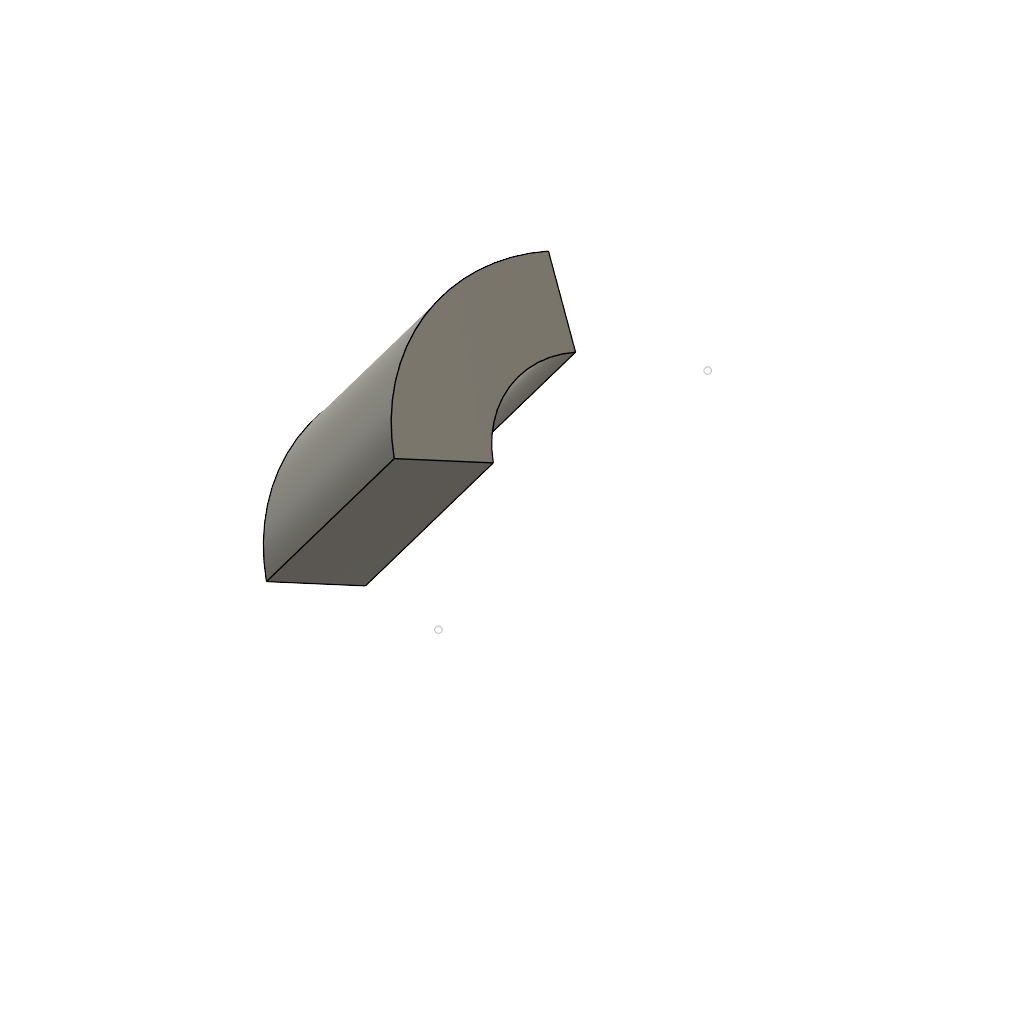
direction_restored (Autodesk Fusion 360 design; units mm, degrees)
part number: 2026-11-27-16-03-31-914
Autodesk Fusion 360 part; units mm, degrees
sketch "AxisSupport" plane through (0, 0, 0) normal (0, 0, 1) x (1, 0, 0)
  point P0 (11, -7)
  point P1 (35, 25)
sketch "RevolveProfile" plane through (0, 0, 0) normal (0, 0, 1) x (1, 0, 0)
  line L0 (8.2, 2.6) -> (19.6, 17.8)
  line L1 (19.6, 17.8) -> (14, 22)
  line L2 (14, 22) -> (2.6, 6.8)
  line L3 (2.6, 6.8) -> (8.2, 2.6)
revolve "UnequalRevolve" add sketch "RevolveProfile" angle 61 about axis through (6.2, -13.4, 0) along (0.6, 0.8, 0) second angle 23
